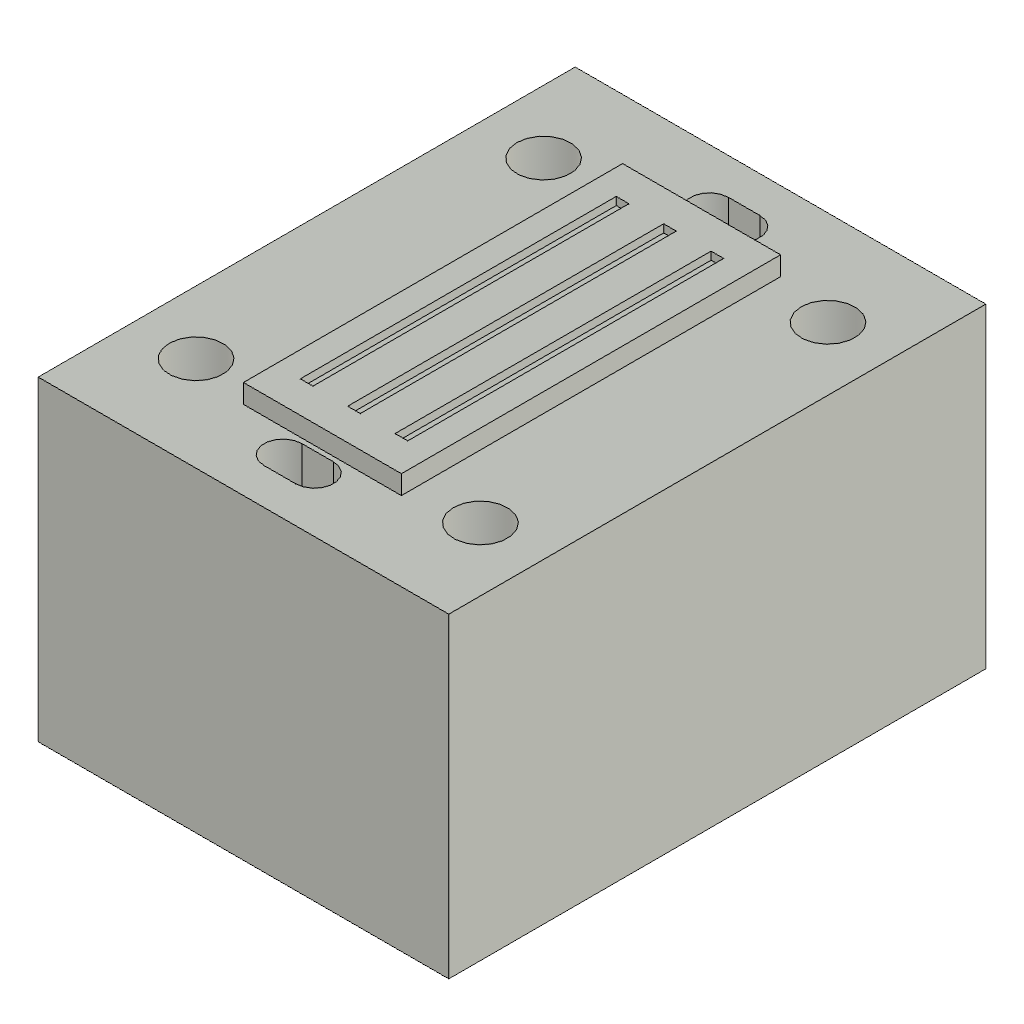
cell_spacer (Autodesk Fusion 360 design; units mm, degrees)
part number: 2026-10-10-17-06-20-098
Autodesk Fusion 360 part; units mm, degrees
sketch "Glue carrier body sketch" plane through (0, 0, 0) normal (0, 0, 1) x (1, 0, 0)
  line L0 (-13, -17) -> (13, -17)
  line L1 (13, -17) -> (13, 17)
  line L2 (13, 17) -> (-13, 17)
  line L3 (-13, 17) -> (-13, -17)
extrude "Glue carrier body" add sketch "Glue carrier body sketch" along normal blind 20
ref_plane "WorkPlane1" through (0, 0, 19.95) normal (0, 0, 1) x (1, 0, 0)
sketch "END ONLY 10x24 glue landing sketch" plane through (0, 0, 19.95) normal (0, 0, 1) x (1, 0, 0)
  line L0 (-5, -12) -> (5, -12)
  line L1 (5, -12) -> (5, 12)
  line L2 (5, 12) -> (-5, 12)
  line L3 (-5, 12) -> (-5, -12)
extrude "END ONLY 10x24 glue landing" add sketch "END ONLY 10x24 glue landing sketch" along normal blind 1.25
ref_plane "WorkPlane2" through (0, 0, 20.7) normal (0, 0, 1) x (1, 0, 0)
sketch "Shallow glue key groove -3 sketch" plane through (0, 0, 20.7) normal (0, 0, 1) x (1, 0, 0)
  line L0 (-3.4, -10) -> (-2.6, -10)
  line L1 (-2.6, -10) -> (-2.6, 10)
  line L2 (-2.6, 10) -> (-3.4, 10)
  line L3 (-3.4, 10) -> (-3.4, -10)
extrude "Shallow glue key groove -3" cut sketch "Shallow glue key groove -3 sketch" along normal blind 0.6
ref_plane "WorkPlane3" through (0, 0, 20.7) normal (0, 0, 1) x (1, 0, 0)
sketch "Shallow glue key groove 0 sketch" plane through (0, 0, 20.7) normal (0, 0, 1) x (1, 0, 0)
  line L0 (-0.4, -10) -> (0.4, -10)
  line L1 (0.4, -10) -> (0.4, 10)
  line L2 (0.4, 10) -> (-0.4, 10)
  line L3 (-0.4, 10) -> (-0.4, -10)
extrude "Shallow glue key groove 0" cut sketch "Shallow glue key groove 0 sketch" along normal blind 0.6
ref_plane "WorkPlane4" through (0, 0, 20.7) normal (0, 0, 1) x (1, 0, 0)
sketch "Shallow glue key groove 3 sketch" plane through (0, 0, 20.7) normal (0, 0, 1) x (1, 0, 0)
  line L0 (2.6, -10) -> (3.4, -10)
  line L1 (3.4, -10) -> (3.4, 10)
  line L2 (3.4, 10) -> (2.6, 10)
  line L3 (2.6, 10) -> (2.6, -10)
extrude "Shallow glue key groove 3" cut sketch "Shallow glue key groove 3 sketch" along normal blind 0.6
ref_plane "WorkPlane5" through (0, 0, -0.05) normal (0, 0, 1) x (1, 0, 0)
sketch "Optional tie return slot -13.5 sketch" plane through (0, 0, -0.05) normal (0, 0, 1) x (1, 0, 0)
  arc A0 (-1, -12.3) -> (-1, -14.7) centre (-1, -13.5) ccw
  line L0 (-1, -12.3) -> (1, -12.3)
  arc A1 (1, -14.7) -> (1, -12.3) centre (1, -13.5) ccw
  line L1 (1, -14.7) -> (-1, -14.7)
extrude "Optional tie return slot -13.5" cut sketch "Optional tie return slot -13.5 sketch" along normal blind 20.1
ref_plane "WorkPlane6" through (0, 0, -0.05) normal (0, 0, 1) x (1, 0, 0)
sketch "Optional tie return slot 13.5 sketch" plane through (0, 0, -0.05) normal (0, 0, 1) x (1, 0, 0)
  arc A0 (-1, 14.7) -> (-1, 12.3) centre (-1, 13.5) ccw
  line L0 (-1, 14.7) -> (1, 14.7)
  arc A1 (1, 12.3) -> (1, 14.7) centre (1, 13.5) ccw
  line L1 (1, 12.3) -> (-1, 12.3)
extrude "Optional tie return slot 13.5" cut sketch "Optional tie return slot 13.5 sketch" along normal blind 20.1
ref_plane "WorkPlane7" through (0, 0, -0.05) normal (0, 0, 1) x (1, 0, 0)
sketch "Pedestal rail bolt -9 -11 sketch" plane through (0, 0, -0.05) normal (0, 0, 1) x (1, 0, 0)
  circle A0 centre (-9, -11) radius 1.7
  dimension "d506" = 3.4
  measures "d506" diameter of A0
extrude "Pedestal rail bolt -9 -11" cut sketch "Pedestal rail bolt -9 -11 sketch" along normal blind 20.1
ref_plane "WorkPlane8" through (0, 0, -0.05) normal (0, 0, 1) x (1, 0, 0)
sketch "Pedestal rail bolt -9 11 sketch" plane through (0, 0, -0.05) normal (0, 0, 1) x (1, 0, 0)
  circle A0 centre (-9, 11) radius 1.7
  dimension "d511" = 3.4
  measures "d511" diameter of A0
extrude "Pedestal rail bolt -9 11" cut sketch "Pedestal rail bolt -9 11 sketch" along normal blind 20.1
ref_plane "WorkPlane9" through (0, 0, -0.05) normal (0, 0, 1) x (1, 0, 0)
sketch "Pedestal rail bolt 9 -11 sketch" plane through (0, 0, -0.05) normal (0, 0, 1) x (1, 0, 0)
  circle A0 centre (9, -11) radius 1.7
  dimension "d516" = 3.4
  measures "d516" diameter of A0
extrude "Pedestal rail bolt 9 -11" cut sketch "Pedestal rail bolt 9 -11 sketch" along normal blind 20.1
ref_plane "WorkPlane10" through (0, 0, -0.05) normal (0, 0, 1) x (1, 0, 0)
sketch "Pedestal rail bolt 9 11 sketch" plane through (0, 0, -0.05) normal (0, 0, 1) x (1, 0, 0)
  circle A0 centre (9, 11) radius 1.7
  dimension "d521" = 3.4
  measures "d521" diameter of A0
extrude "Pedestal rail bolt 9 11" cut sketch "Pedestal rail bolt 9 11 sketch" along normal blind 20.1
equation "d506 = m3Clearance"
equation "d511 = m3Clearance"
equation "d516 = m3Clearance"
equation "d521 = m3Clearance"
equation "m3Clearance = 3.4 mm" comment "Root registration and tip adapter holes"
named bodies: "cell_spacer - printable solid"
